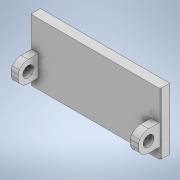
# Autodesk Inventor part: sharp_baza
Saved by Autodesk Inventor 2020 (Build 240168000, 168)
## iProperties
Created: 2023-10-29
Part Number: sharp_baza
Material: Generic
Document SubType Name: Modeling
Designer: user
Density: 1 g/cm^3
Appearance: Default
Author: user
Autodesk Inventor part; units mm, degrees
ref_plane "YZ Plane" through (0, 0, 0) normal (1, 0, 0) x (0, 1, 0)
ref_plane "XZ Plane" through (0, 0, 0) normal (0, 1, 0) x (-1, 0, 0)
ref_plane "XY Plane" through (0, 0, 0) normal (0, 0, 1) x (1, 0, 0)
sketch "Sketch1" plane through (0, 0, 0) normal (0, 0, 1) x (1, 0, 0)
  line L0 (-27.1716, 20.5434) -> (12.8284, 20.5434)
  line L1 (12.8284, 20.5434) -> (12.8284, 1.5434)
  line L2 (12.8284, 1.5434) -> (-27.1716, 1.5434)
  line L3 (-27.1716, 1.5434) -> (-27.1716, 20.5434)
  point P0 (0, 0)
  dimension "d0" = 40
  dimension "d1" = 19
  constraints: 8 end point, 2 parallel, 1 horizontal, 1 perpendicular
  measures "d0" distance of L1.end L2.end
  measures "d1" distance of L0.end L1.end
extrude "Extrusion1" add sketch "Sketch1" along normal blind 3
sketch "Sketch2" plane through (-27.1716, 1.5434, 0) normal (-1, 0, 0) x (0, 0, 1)
  line L0 (0, 19) -> (0, 0) projected
  line L1 (0, 0) -> (3, 0) projected
  line L2 (3, 19) -> (3, 0) projected
  line L3 (0, 19) -> (3, 19) projected
  arc A0 (9.3, 7.6225) -> (9.3, 5.3775) centre (6.25, 6.5) ccw
  circle A1 centre (6.25, 6.5) radius 1.65
  line L4 (6.25, 9.75) -> (3, 9.75)
  line L5 (3, 19) -> (3, 0) projected
  line L6 (6.25, 3.25) -> (3, 3.25)
  line L7 (9.3, 7.6225) -> (9.3, 5.3775)
  point P0 (0, -1.5434)
  point P1 (3, 6.5)
  dimension "d4" = 6.5
  dimension "d5" = 3.3
  dimension "d6" = 12.5
  constraints: 6 end point, 4 point on circle, 2 centre point, 2 point on line, 1 coincident, 1 horizontal, 1 parallel, 1 tangent
  measures "d4" diameter of A0
  measures "d5" diameter of A1
  measures "d6" distance from line of L3 A0.centre
extrude "Extrusion2" add sketch "Sketch2" against normal blind 40 contours L4 A0 L2 | L2 A0 L6 | A0 L7
sketch "Sketch3" plane through (-27.1716, 1.5434, 0) normal (0, -1, 0) x (1, 0, 0)
  line L0 (0, 0) -> (40, 0) projected
  line L1 (40, 0) -> (40, 3) projected
  line L2 (0, 3) -> (40, 3) projected
  line L3 (0, 0) -> (0, 3) projected
  line L4 (40, 3) -> (0, 3) projected
  line L5 (0, 0) -> (0, 3) projected
  line L6 (0, 3) -> (0.3, 3)
  line L7 (0.3, 3) -> (0.3, 10.5018)
  line L8 (0.3, 10.5018) -> (0, 10.5018)
  line L9 (0, 10.5018) -> (0, 3)
  line L10 (2.5, 3) -> (37.2, 3)
  line L11 (37.2, 3) -> (37.2, 12.0356)
  line L12 (37.2, 12.0356) -> (2.5, 12.0356)
  line L13 (2.5, 12.0356) -> (2.5, 3)
  line L14 (40, 0) -> (40, 3) projected
  line L15 (40, 3) -> (39.7, 3)
  line L16 (39.7, 3) -> (39.7, 10.0944)
  line L17 (39.7, 10.0944) -> (40, 10.0944)
  line L18 (40, 10.0944) -> (40, 3)
  line L19 (0, 3) -> (0.3, 3)
  line L20 (0.3, 3) -> (0.3, 2.7)
  line L21 (0.3, 2.7) -> (0, 2.7)
  line L22 (0, 2.7) -> (0, 3)
  line L23 (39.7, 3) -> (40, 3)
  line L24 (40, 3) -> (40, 2.7)
  line L25 (40, 2.7) -> (39.7, 2.7)
  line L26 (39.7, 2.7) -> (39.7, 3)
  point P0 (27.1716, 0)
  dimension "d9" = 0.3
  dimension "d10" = 0.3
  dimension "d13" = 2.5
  dimension "d14" = 2.5
  dimension "d23" = 0.3
  dimension "d24" = 0.3
  constraints: 40 end point, 10 parallel, 5 horizontal, 5 perpendicular, 5 point on line
  measures "d9" distance from line of L1 point (39.7, 3)
  measures "d10" distance from line of L3 point (0.3, 3)
  measures "d13" distance of L2.start L10.start
  measures "d14" distance of point (39.7, 3) point (37.2, 3)
  measures "d23" distance of L19.end L20.end
  measures "d24" distance of L23.end L24.end
extrude "Extrusion3" cut sketch "Sketch3" against normal blind 19 contours L3 L2 L20 L21 | L25 L26 L2 L1 | L9 L8 L7 L2 | L2 L16 L17 L18 | L13 L12 L11 L2
fillet "Fillet1" radius 2 4 edges at (11.2784, 9.1659, 9.3) (11.2784, 6.9209, 9.3) (-25.7716, 6.9209, 9.3) (-25.7716, 9.1659, 9.3)
body "Solid1"
